Autodesk Fusion 360 part; units mm, degrees
(part 3 of 10)
sketch "Sloped T channel 0 sketch (4)" plane through (22, 0, 0) normal (1, 0, 0) x (0, 0, -1) in component "Horizontal tie 00 - measured sloped-slot approximation"
  line L0 (-15, 8.86) -> (-16.5, 8.86)
  line L1 (-16.5, 8.86) -> (-16.5, 6.5)
  line L2 (-16.5, 6.5) -> (-18.55, 6.5)
  line L3 (-18.55, 6.5) -> (-21.2, 9.15)
  line L4 (-21.2, 9.15) -> (-21.2, 14.85)
  line L5 (-21.2, 14.85) -> (-18.55, 17.5)
  line L6 (-18.55, 17.5) -> (-16.5, 17.5)
  line L7 (-16.5, 17.5) -> (-16.5, 15.14)
  line L8 (-16.5, 15.14) -> (-15, 15.14)
  line L9 (-15, 15.14) -> (-15, 8.86)
  dimension "d922" = 15
  dimension "d923" = 8.86
  dimension "d924" = 16.5
  dimension "d925" = 6.5
  dimension "d926" = 18.55
  dimension "d927" = 21.2
  dimension "d928" = 9.15
  dimension "d929" = 14.85
  dimension "d930" = 17.5
  dimension "d931" = 15.14
  constraint horizontal L0.start L0.end
  constraint vertical L0.end L1.end
  constraint horizontal L1.end L2.end
  constraint vertical L3.end L4.end
  constraint vertical L2.end L5.end
  constraint vertical L1.end L6.end
  constraint horizontal L5.end L6.end
  constraint vertical L6.end L7.end
  constraint vertical L0.start L8.end
  constraint horizontal L7.end L8.end
  measures "d922" horizontal distance of origin L0.start
  measures "d923" vertical distance of origin L0.start
  measures "d924" horizontal distance of origin L0.end
  measures "d925" vertical distance of origin L1.end
  measures "d926" horizontal distance of origin L2.end
  measures "d927" horizontal distance of origin L3.end
  measures "d928" vertical distance of origin L3.end
  measures "d929" vertical distance of origin L4.end
  measures "d930" vertical distance of origin L5.end
  measures "d931" vertical distance of origin L7.end
extrude "Sloped T channel 0'''" cut sketch "Sloped T channel 0 sketch (4)" along normal blind 88 bodies 8 in component "Horizontal tie 00 - measured sloped-slot approximation"
ref_plane "WorkPlane3" through (22, 0, 0) normal (1, 0, 0) x (0, 1, 0) in component "Horizontal tie 00 - measured sloped-slot approximation"
sketch "Sloped T channel 1 sketch (4)" plane through (22, 0, 0) normal (1, 0, 0) x (0, 0, -1) in component "Horizontal tie 00 - measured sloped-slot approximation"
  line L0 (-21.86, 22) -> (-21.86, 20.5)
  line L1 (-21.86, 20.5) -> (-19.5, 20.5)
  line L2 (-19.5, 20.5) -> (-19.5, 18.45)
  line L3 (-19.5, 18.45) -> (-22.15, 15.8)
  line L4 (-22.15, 15.8) -> (-27.85, 15.8)
  line L5 (-27.85, 15.8) -> (-30.5, 18.45)
  line L6 (-30.5, 18.45) -> (-30.5, 20.5)
  line L7 (-30.5, 20.5) -> (-28.14, 20.5)
  line L8 (-28.14, 20.5) -> (-28.14, 22)
  line L9 (-28.14, 22) -> (-21.86, 22)
  dimension "d936" = 21.86
  dimension "d937" = 22
  dimension "d938" = 20.5
  dimension "d939" = 19.5
  dimension "d940" = 18.45
  dimension "d941" = 22.15
  dimension "d942" = 15.8
  dimension "d943" = 27.85
  dimension "d944" = 30.5
  dimension "d945" = 28.14
  constraint vertical L0.start L0.end
  constraint horizontal L0.end L1.end
  constraint vertical L1.end L2.end
  constraint horizontal L3.end L4.end
  constraint horizontal L2.end L5.end
  constraint vertical L5.end L6.end
  constraint horizontal L1.end L6.end
  constraint horizontal L6.end L7.end
  constraint vertical L7.end L8.end
  constraint horizontal L0.start L8.end
  measures "d936" horizontal distance of origin L0.start
  measures "d937" vertical distance of origin L0.start
  measures "d938" vertical distance of origin L0.end
  measures "d939" horizontal distance of origin L1.end
  measures "d940" vertical distance of origin L2.end
  measures "d941" horizontal distance of origin L3.end
  measures "d942" vertical distance of origin L3.end
  measures "d943" horizontal distance of origin L4.end
  measures "d944" horizontal distance of origin L5.end
  measures "d945" horizontal distance of origin L7.end
extrude "Sloped T channel 1'''" cut sketch "Sloped T channel 1 sketch (4)" along normal blind 88 bodies 8 in component "Horizontal tie 00 - measured sloped-slot approximation"
ref_plane "WorkPlane4" through (22, 0, 0) normal (1, 0, 0) x (0, 1, 0) in component "Horizontal tie 00 - measured sloped-slot approximation"
sketch "Sloped T channel 2 sketch (4)" plane through (22, 0, 0) normal (1, 0, 0) x (0, 0, -1) in component "Horizontal tie 00 - measured sloped-slot approximation"
  line L0 (-35, 15.14) -> (-33.5, 15.14)
  line L1 (-33.5, 15.14) -> (-33.5, 17.5)
  line L2 (-33.5, 17.5) -> (-31.45, 17.5)
  line L3 (-31.45, 17.5) -> (-28.8, 14.85)
  line L4 (-28.8, 14.85) -> (-28.8, 9.15)
  line L5 (-28.8, 9.15) -> (-31.45, 6.5)
  line L6 (-31.45, 6.5) -> (-33.5, 6.5)
  line L7 (-33.5, 6.5) -> (-33.5, 8.86)
  line L8 (-33.5, 8.86) -> (-35, 8.86)
  line L9 (-35, 8.86) -> (-35, 15.14)
  dimension "d950" = 35
  dimension "d951" = 15.14
  dimension "d952" = 33.5
  dimension "d953" = 17.5
  dimension "d954" = 31.45
  dimension "d955" = 28.8
  dimension "d956" = 14.85
  dimension "d957" = 9.15
  dimension "d958" = 6.5
  dimension "d959" = 8.86
  constraint horizontal L0.start L0.end
  constraint vertical L0.end L1.end
  constraint horizontal L1.end L2.end
  constraint vertical L3.end L4.end
  constraint vertical L2.end L5.end
  constraint vertical L1.end L6.end
  constraint horizontal L5.end L6.end
  constraint vertical L6.end L7.end
  constraint vertical L0.start L8.end
  constraint horizontal L7.end L8.end
  measures "d950" horizontal distance of origin L0.start
  measures "d951" vertical distance of origin L0.start
  measures "d952" horizontal distance of origin L0.end
  measures "d953" vertical distance of origin L1.end
  measures "d954" horizontal distance of origin L2.end
  measures "d955" horizontal distance of origin L3.end
  measures "d956" vertical distance of origin L3.end
  measures "d957" vertical distance of origin L4.end
  measures "d958" vertical distance of origin L5.end
  measures "d959" vertical distance of origin L7.end
extrude "Sloped T channel 2'''" cut sketch "Sloped T channel 2 sketch (4)" along normal blind 88 bodies 8 in component "Horizontal tie 00 - measured sloped-slot approximation"
ref_plane "WorkPlane5" through (22, 0, 0) normal (1, 0, 0) x (0, 1, 0) in component "Horizontal tie 00 - measured sloped-slot approximation"
sketch "Sloped T channel 3 sketch (4)" plane through (22, 0, 0) normal (1, 0, 0) x (0, 0, -1) in component "Horizontal tie 00 - measured sloped-slot approximation"
  line L0 (-28.14, 2) -> (-28.14, 3.5)
  line L1 (-28.14, 3.5) -> (-30.5, 3.5)
  line L2 (-30.5, 3.5) -> (-30.5, 5.55)
  line L3 (-30.5, 5.55) -> (-27.85, 8.2)
  line L4 (-27.85, 8.2) -> (-22.15, 8.2)
  line L5 (-22.15, 8.2) -> (-19.5, 5.55)
  line L6 (-19.5, 5.55) -> (-19.5, 3.5)
  line L7 (-19.5, 3.5) -> (-21.86, 3.5)
  line L8 (-21.86, 3.5) -> (-21.86, 2)
  line L9 (-21.86, 2) -> (-28.14, 2)
  dimension "d964" = 28.14
  dimension "d965" = 2
  dimension "d966" = 3.5
  dimension "d967" = 30.5
  dimension "d968" = 5.55
  dimension "d969" = 27.85
  dimension "d970" = 8.2
  dimension "d971" = 22.15
  dimension "d972" = 19.5
  dimension "d973" = 21.86
  constraint vertical L0.start L0.end
  constraint horizontal L0.end L1.end
  constraint vertical L1.end L2.end
  constraint horizontal L3.end L4.end
  constraint horizontal L2.end L5.end
  constraint vertical L5.end L6.end
  constraint horizontal L1.end L6.end
  constraint horizontal L6.end L7.end
  constraint vertical L7.end L8.end
  constraint horizontal L0.start L8.end
  measures "d964" horizontal distance of origin L0.start
  measures "d965" vertical distance of origin L0.start
  measures "d966" vertical distance of origin L0.end
  measures "d967" horizontal distance of origin L1.end
  measures "d968" vertical distance of origin L2.end
  measures "d969" horizontal distance of origin L3.end
  measures "d970" vertical distance of origin L3.end
  measures "d971" horizontal distance of origin L4.end
  measures "d972" horizontal distance of origin L5.end
  measures "d973" horizontal distance of origin L7.end
extrude "Sloped T channel 3'''" cut sketch "Sloped T channel 3 sketch (4)" along normal blind 88 bodies 8 in component "Horizontal tie 00 - measured sloped-slot approximation"
ref_plane "WorkPlane6" through (22, 0, 0) normal (1, 0, 0) x (0, 1, 0) in component "Horizontal tie 00 - measured sloped-slot approximation"
sketch "Reference center bore sketch (4)" plane through (22, 0, 0) normal (1, 0, 0) x (0, 0, -1) in component "Horizontal tie 00 - measured sloped-slot approximation"
  circle A0 centre (-25, 12) radius 2.5
  dimension "d978" = 25
  dimension "d979" = 12
  dimension "d980" = 5
  measures "d978" horizontal distance of origin A0.centre
  measures "d979" vertical distance of origin A0.centre
  measures "d980" diameter of A0
extrude "Reference center bore'''" cut sketch "Reference center bore sketch (4)" along normal blind 88 bodies 8 in component "Horizontal tie 00 - measured sloped-slot approximation"
ref_plane "WorkPlane1" through (130, 0, 0) normal (1, 0, 0) x (0, 1, 0) in component "Horizontal tie 10 - measured sloped-slot approximation"
sketch "Profile blank sketch (5)" plane through (130, 0, 0) normal (1, 0, 0) x (0, 0, -1) in component "Horizontal tie 10 - measured sloped-slot approximation"
  line L0 (-15, 2) -> (-15, 22)
  line L1 (-15, 22) -> (-35, 22)
  line L2 (-35, 22) -> (-35, 2)
  line L3 (-35, 2) -> (-15, 2)
  dimension "d985" = 15
  dimension "d986" = 2
  dimension "d987" = 22
  dimension "d988" = 35
  constraint vertical L0.start L0.end
  constraint horizontal L0.end L1.end
  constraint vertical L1.end L2.end
  constraint horizontal L0.start L2.end
  measures "d985" horizontal distance of origin L0.start
  measures "d986" vertical distance of origin L0.start
  measures "d987" vertical distance of origin L0.end
  measures "d988" horizontal distance of origin L1.end
extrude "Profile blank''''" add sketch "Profile blank sketch (5)" along normal blind 88 separate body makes body 9 in component "Horizontal tie 10 - measured sloped-slot approximation"
ref_plane "WorkPlane2" through (130, 0, 0) normal (1, 0, 0) x (0, 1, 0) in component "Horizontal tie 10 - measured sloped-slot approximation"
sketch "Sloped T channel 0 sketch (5)" plane through (130, 0, 0) normal (1, 0, 0) x (0, 0, -1) in component "Horizontal tie 10 - measured sloped-slot approximation"
  line L0 (-15, 8.86) -> (-16.5, 8.86)
  line L1 (-16.5, 8.86) -> (-16.5, 6.5)
  line L2 (-16.5, 6.5) -> (-18.55, 6.5)
  line L3 (-18.55, 6.5) -> (-21.2, 9.15)
  line L4 (-21.2, 9.15) -> (-21.2, 14.85)
  line L5 (-21.2, 14.85) -> (-18.55, 17.5)
  line L6 (-18.55, 17.5) -> (-16.5, 17.5)
  line L7 (-16.5, 17.5) -> (-16.5, 15.14)
  line L8 (-16.5, 15.14) -> (-15, 15.14)
  line L9 (-15, 15.14) -> (-15, 8.86)
  dimension "d993" = 15
  dimension "d994" = 8.86
  dimension "d995" = 16.5
  dimension "d996" = 6.5
  dimension "d997" = 18.55
  dimension "d998" = 21.2
  dimension "d999" = 9.15
  dimension "d1000" = 14.85
  dimension "d1001" = 17.5
  dimension "d1002" = 15.14
  constraint horizontal L0.start L0.end
  constraint vertical L0.end L1.end
  constraint horizontal L1.end L2.end
  constraint vertical L3.end L4.end
  constraint vertical L2.end L5.end
  constraint vertical L1.end L6.end
  constraint horizontal L5.end L6.end
  constraint vertical L6.end L7.end
  constraint vertical L0.start L8.end
  constraint horizontal L7.end L8.end
  measures "d993" horizontal distance of origin L0.start
  measures "d994" vertical distance of origin L0.start
  measures "d995" horizontal distance of origin L0.end
  measures "d996" vertical distance of origin L1.end
  measures "d997" horizontal distance of origin L2.end
  measures "d998" horizontal distance of origin L3.end
  measures "d999" vertical distance of origin L3.end
  measures "d1000" vertical distance of origin L4.end
  measures "d1001" vertical distance of origin L5.end
  measures "d1002" vertical distance of origin L7.end
extrude "Sloped T channel 0''''" cut sketch "Sloped T channel 0 sketch (5)" along normal blind 88 bodies 9 in component "Horizontal tie 10 - measured sloped-slot approximation"
ref_plane "WorkPlane3" through (130, 0, 0) normal (1, 0, 0) x (0, 1, 0) in component "Horizontal tie 10 - measured sloped-slot approximation"
sketch "Sloped T channel 1 sketch (5)" plane through (130, 0, 0) normal (1, 0, 0) x (0, 0, -1) in component "Horizontal tie 10 - measured sloped-slot approximation"
  line L0 (-21.86, 22) -> (-21.86, 20.5)
  line L1 (-21.86, 20.5) -> (-19.5, 20.5)
  line L2 (-19.5, 20.5) -> (-19.5, 18.45)
  line L3 (-19.5, 18.45) -> (-22.15, 15.8)
  line L4 (-22.15, 15.8) -> (-27.85, 15.8)
  line L5 (-27.85, 15.8) -> (-30.5, 18.45)
  line L6 (-30.5, 18.45) -> (-30.5, 20.5)
  line L7 (-30.5, 20.5) -> (-28.14, 20.5)
  line L8 (-28.14, 20.5) -> (-28.14, 22)
  line L9 (-28.14, 22) -> (-21.86, 22)
  dimension "d1007" = 21.86
  dimension "d1008" = 22
  dimension "d1009" = 20.5
  dimension "d1010" = 19.5
  dimension "d1011" = 18.45
  dimension "d1012" = 22.15
  dimension "d1013" = 15.8
  dimension "d1014" = 27.85
  dimension "d1015" = 30.5
  dimension "d1016" = 28.14
  constraint vertical L0.start L0.end
  constraint horizontal L0.end L1.end
  constraint vertical L1.end L2.end
  constraint horizontal L3.end L4.end
  constraint horizontal L2.end L5.end
  constraint vertical L5.end L6.end
  constraint horizontal L1.end L6.end
  constraint horizontal L6.end L7.end
  constraint vertical L7.end L8.end
  constraint horizontal L0.start L8.end
  measures "d1007" horizontal distance of origin L0.start
  measures "d1008" vertical distance of origin L0.start
  measures "d1009" vertical distance of origin L0.end
  measures "d1010" horizontal distance of origin L1.end
  measures "d1011" vertical distance of origin L2.end
  measures "d1012" horizontal distance of origin L3.end
  measures "d1013" vertical distance of origin L3.end
  measures "d1014" horizontal distance of origin L4.end
  measures "d1015" horizontal distance of origin L5.end
  measures "d1016" horizontal distance of origin L7.end
extrude "Sloped T channel 1''''" cut sketch "Sloped T channel 1 sketch (5)" along normal blind 88 bodies 9 in component "Horizontal tie 10 - measured sloped-slot approximation"
ref_plane "WorkPlane4" through (130, 0, 0) normal (1, 0, 0) x (0, 1, 0) in component "Horizontal tie 10 - measured sloped-slot approximation"
sketch "Sloped T channel 2 sketch (5)" plane through (130, 0, 0) normal (1, 0, 0) x (0, 0, -1) in component "Horizontal tie 10 - measured sloped-slot approximation"
  line L0 (-35, 15.14) -> (-33.5, 15.14)
  line L1 (-33.5, 15.14) -> (-33.5, 17.5)
  line L2 (-33.5, 17.5) -> (-31.45, 17.5)
  line L3 (-31.45, 17.5) -> (-28.8, 14.85)
  line L4 (-28.8, 14.85) -> (-28.8, 9.15)
  line L5 (-28.8, 9.15) -> (-31.45, 6.5)
  line L6 (-31.45, 6.5) -> (-33.5, 6.5)
  line L7 (-33.5, 6.5) -> (-33.5, 8.86)
  line L8 (-33.5, 8.86) -> (-35, 8.86)
  line L9 (-35, 8.86) -> (-35, 15.14)
  dimension "d1021" = 35
  dimension "d1022" = 15.14
  dimension "d1023" = 33.5
  dimension "d1024" = 17.5
  dimension "d1025" = 31.45
  dimension "d1026" = 28.8
  dimension "d1027" = 14.85
  dimension "d1028" = 9.15
  dimension "d1029" = 6.5
  dimension "d1030" = 8.86
  constraint horizontal L0.start L0.end
  constraint vertical L0.end L1.end
  constraint horizontal L1.end L2.end
  constraint vertical L3.end L4.end
  constraint vertical L2.end L5.end
  constraint vertical L1.end L6.end
  constraint horizontal L5.end L6.end
  constraint vertical L6.end L7.end
  constraint vertical L0.start L8.end
  constraint horizontal L7.end L8.end
  measures "d1021" horizontal distance of origin L0.start
  measures "d1022" vertical distance of origin L0.start
  measures "d1023" horizontal distance of origin L0.end
  measures "d1024" vertical distance of origin L1.end
  measures "d1025" horizontal distance of origin L2.end
  measures "d1026" horizontal distance of origin L3.end
  measures "d1027" vertical distance of origin L3.end
  measures "d1028" vertical distance of origin L4.end
  measures "d1029" vertical distance of origin L5.end
  measures "d1030" vertical distance of origin L7.end
extrude "Sloped T channel 2''''" cut sketch "Sloped T channel 2 sketch (5)" along normal blind 88 bodies 9 in component "Horizontal tie 10 - measured sloped-slot approximation"
ref_plane "WorkPlane5" through (130, 0, 0) normal (1, 0, 0) x (0, 1, 0) in component "Horizontal tie 10 - measured sloped-slot approximation"
sketch "Sloped T channel 3 sketch (5)" plane through (130, 0, 0) normal (1, 0, 0) x (0, 0, -1) in component "Horizontal tie 10 - measured sloped-slot approximation"
  line L0 (-28.14, 2) -> (-28.14, 3.5)
  line L1 (-28.14, 3.5) -> (-30.5, 3.5)
  line L2 (-30.5, 3.5) -> (-30.5, 5.55)
  line L3 (-30.5, 5.55) -> (-27.85, 8.2)
  line L4 (-27.85, 8.2) -> (-22.15, 8.2)
  line L5 (-22.15, 8.2) -> (-19.5, 5.55)
  line L6 (-19.5, 5.55) -> (-19.5, 3.5)
  line L7 (-19.5, 3.5) -> (-21.86, 3.5)
  line L8 (-21.86, 3.5) -> (-21.86, 2)
  line L9 (-21.86, 2) -> (-28.14, 2)
  dimension "d1035" = 28.14
  dimension "d1036" = 2
  dimension "d1037" = 3.5
  dimension "d1038" = 30.5
  dimension "d1039" = 5.55
  dimension "d1040" = 27.85
  dimension "d1041" = 8.2
  dimension "d1042" = 22.15
  dimension "d1043" = 19.5
  dimension "d1044" = 21.86
  constraint vertical L0.start L0.end
  constraint horizontal L0.end L1.end
  constraint vertical L1.end L2.end
  constraint horizontal L3.end L4.end
  constraint horizontal L2.end L5.end
  constraint vertical L5.end L6.end
  constraint horizontal L1.end L6.end
  constraint horizontal L6.end L7.end
  constraint vertical L7.end L8.end
  constraint horizontal L0.start L8.end
  measures "d1035" horizontal distance of origin L0.start
  measures "d1036" vertical distance of origin L0.start
  measures "d1037" vertical distance of origin L0.end
  measures "d1038" horizontal distance of origin L1.end
  measures "d1039" vertical distance of origin L2.end
  measures "d1040" horizontal distance of origin L3.end
  measures "d1041" vertical distance of origin L3.end
  measures "d1042" horizontal distance of origin L4.end
  measures "d1043" horizontal distance of origin L5.end
  measures "d1044" horizontal distance of origin L7.end
extrude "Sloped T channel 3''''" cut sketch "Sloped T channel 3 sketch (5)" along normal blind 88 bodies 9 in component "Horizontal tie 10 - measured sloped-slot approximation"
ref_plane "WorkPlane6" through (130, 0, 0) normal (1, 0, 0) x (0, 1, 0) in component "Horizontal tie 10 - measured sloped-slot approximation"
sketch "Reference center bore sketch (5)" plane through (130, 0, 0) normal (1, 0, 0) x (0, 0, -1) in component "Horizontal tie 10 - measured sloped-slot approximation"
  circle A0 centre (-25, 12) radius 2.5
  dimension "d1049" = 25
  dimension "d1050" = 12
  dimension "d1051" = 5
  measures "d1049" horizontal distance of origin A0.centre
  measures "d1050" vertical distance of origin A0.centre
  measures "d1051" diameter of A0
extrude "Reference center bore''''" cut sketch "Reference center bore sketch (5)" along normal blind 88 bodies 9 in component "Horizontal tie 10 - measured sloped-slot approximation"
ref_plane "WorkPlane1" through (22, 0, 0) normal (1, 0, 0) x (0, 1, 0) in component "Horizontal tie 01 - measured sloped-slot approximation"
sketch "Profile blank sketch (6)" plane through (22, 0, 0) normal (1, 0, 0) x (0, 0, -1) in component "Horizontal tie 01 - measured sloped-slot approximation"
  line L0 (-15, 218) -> (-15, 238)
  line L1 (-15, 238) -> (-35, 238)
  line L2 (-35, 238) -> (-35, 218)
  line L3 (-35, 218) -> (-15, 218)
  dimension "d1056" = 15
  dimension "d1057" = 218
  dimension "d1058" = 238
  dimension "d1059" = 35
  constraint vertical L0.start L0.end
  constraint horizontal L0.end L1.end
  constraint vertical L1.end L2.end
  constraint horizontal L0.start L2.end
  measures "d1056" horizontal distance of origin L0.start
  measures "d1057" vertical distance of origin L0.start
  measures "d1058" vertical distance of origin L0.end
  measures "d1059" horizontal distance of origin L1.end
extrude "Profile blank'''''" add sketch "Profile blank sketch (6)" along normal blind 88 separate body makes body 10 in component "Horizontal tie 01 - measured sloped-slot approximation"
ref_plane "WorkPlane2" through (22, 0, 0) normal (1, 0, 0) x (0, 1, 0) in component "Horizontal tie 01 - measured sloped-slot approximation"
sketch "Sloped T channel 0 sketch (6)" plane through (22, 0, 0) normal (1, 0, 0) x (0, 0, -1) in component "Horizontal tie 01 - measured sloped-slot approximation"
  line L0 (-15, 224.86) -> (-16.5, 224.86)
  line L1 (-16.5, 224.86) -> (-16.5, 222.5)
  line L2 (-16.5, 222.5) -> (-18.55, 222.5)
  line L3 (-18.55, 222.5) -> (-21.2, 225.15)
  line L4 (-21.2, 225.15) -> (-21.2, 230.85)
  line L5 (-21.2, 230.85) -> (-18.55, 233.5)
  line L6 (-18.55, 233.5) -> (-16.5, 233.5)
  line L7 (-16.5, 233.5) -> (-16.5, 231.14)
  line L8 (-16.5, 231.14) -> (-15, 231.14)
  line L9 (-15, 231.14) -> (-15, 224.86)
  dimension "d1064" = 15
  dimension "d1065" = 224.86
  dimension "d1066" = 16.5
  dimension "d1067" = 222.5
  dimension "d1068" = 18.55
  dimension "d1069" = 21.2
  dimension "d1070" = 225.15
  dimension "d1071" = 230.85
  dimension "d1072" = 233.5
  dimension "d1073" = 231.14
  constraint horizontal L0.start L0.end
  constraint vertical L0.end L1.end
  constraint horizontal L1.end L2.end
  constraint vertical L3.end L4.end
  constraint vertical L2.end L5.end
  constraint vertical L1.end L6.end
  constraint horizontal L5.end L6.end
  constraint vertical L6.end L7.end
  constraint vertical L0.start L8.end
  constraint horizontal L7.end L8.end
  measures "d1064" horizontal distance of origin L0.start
  measures "d1065" vertical distance of origin L0.start
  measures "d1066" horizontal distance of origin L0.end
  measures "d1067" vertical distance of origin L1.end
  measures "d1068" horizontal distance of origin L2.end
  measures "d1069" horizontal distance of origin L3.end
  measures "d1070" vertical distance of origin L3.end
  measures "d1071" vertical distance of origin L4.end
  measures "d1072" vertical distance of origin L5.end
  measures "d1073" vertical distance of origin L7.end
extrude "Sloped T channel 0'''''" cut sketch "Sloped T channel 0 sketch (6)" along normal blind 88 bodies 10 in component "Horizontal tie 01 - measured sloped-slot approximation"
ref_plane "WorkPlane3" through (22, 0, 0) normal (1, 0, 0) x (0, 1, 0) in component "Horizontal tie 01 - measured sloped-slot approximation"
sketch "Sloped T channel 1 sketch (6)" plane through (22, 0, 0) normal (1, 0, 0) x (0, 0, -1) in component "Horizontal tie 01 - measured sloped-slot approximation"
  line L0 (-21.86, 238) -> (-21.86, 236.5)
  line L1 (-21.86, 236.5) -> (-19.5, 236.5)
  line L2 (-19.5, 236.5) -> (-19.5, 234.45)
  line L3 (-19.5, 234.45) -> (-22.15, 231.8)
  line L4 (-22.15, 231.8) -> (-27.85, 231.8)
  line L5 (-27.85, 231.8) -> (-30.5, 234.45)
  line L6 (-30.5, 234.45) -> (-30.5, 236.5)
  line L7 (-30.5, 236.5) -> (-28.14, 236.5)
  line L8 (-28.14, 236.5) -> (-28.14, 238)
  line L9 (-28.14, 238) -> (-21.86, 238)
  dimension "d1078" = 21.86
  dimension "d1079" = 238
  dimension "d1080" = 236.5
  dimension "d1081" = 19.5
  dimension "d1082" = 234.45
  dimension "d1083" = 22.15
  dimension "d1084" = 231.8
  dimension "d1085" = 27.85
  dimension "d1086" = 30.5
  dimension "d1087" = 28.14
  constraint vertical L0.start L0.end
  constraint horizontal L0.end L1.end
  constraint vertical L1.end L2.end
  constraint horizontal L3.end L4.end
  constraint horizontal L2.end L5.end
  constraint vertical L5.end L6.end
  constraint horizontal L1.end L6.end
  constraint horizontal L6.end L7.end
  constraint vertical L7.end L8.end
  constraint horizontal L0.start L8.end
  measures "d1078" horizontal distance of origin L0.start
  measures "d1079" vertical distance of origin L0.start
  measures "d1080" vertical distance of origin L0.end
  measures "d1081" horizontal distance of origin L1.end
  measures "d1082" vertical distance of origin L2.end
  measures "d1083" horizontal distance of origin L3.end
  measures "d1084" vertical distance of origin L3.end
  measures "d1085" horizontal distance of origin L4.end
  measures "d1086" horizontal distance of origin L5.end
  measures "d1087" horizontal distance of origin L7.end
extrude "Sloped T channel 1'''''" cut sketch "Sloped T channel 1 sketch (6)" along normal blind 88 bodies 10 in component "Horizontal tie 01 - measured sloped-slot approximation"
ref_plane "WorkPlane4" through (22, 0, 0) normal (1, 0, 0) x (0, 1, 0) in component "Horizontal tie 01 - measured sloped-slot approximation"
sketch "Sloped T channel 2 sketch (6)" plane through (22, 0, 0) normal (1, 0, 0) x (0, 0, -1) in component "Horizontal tie 01 - measured sloped-slot approximation"
  line L0 (-35, 231.14) -> (-33.5, 231.14)
  line L1 (-33.5, 231.14) -> (-33.5, 233.5)
  line L2 (-33.5, 233.5) -> (-31.45, 233.5)
  line L3 (-31.45, 233.5) -> (-28.8, 230.85)
  line L4 (-28.8, 230.85) -> (-28.8, 225.15)
  line L5 (-28.8, 225.15) -> (-31.45, 222.5)
  line L6 (-31.45, 222.5) -> (-33.5, 222.5)
  line L7 (-33.5, 222.5) -> (-33.5, 224.86)
  line L8 (-33.5, 224.86) -> (-35, 224.86)
  line L9 (-35, 224.86) -> (-35, 231.14)
  dimension "d1092" = 35
  dimension "d1093" = 231.14
  dimension "d1094" = 33.5
  dimension "d1095" = 233.5
  dimension "d1096" = 31.45
  dimension "d1097" = 28.8
  dimension "d1098" = 230.85
  dimension "d1099" = 225.15
  dimension "d1100" = 222.5
  dimension "d1101" = 224.86
  constraint horizontal L0.start L0.end
  constraint vertical L0.end L1.end
  constraint horizontal L1.end L2.end
  constraint vertical L3.end L4.end
  constraint vertical L2.end L5.end
  constraint vertical L1.end L6.end
  constraint horizontal L5.end L6.end
  constraint vertical L6.end L7.end
  constraint vertical L0.start L8.end
  constraint horizontal L7.end L8.end
  measures "d1092" horizontal distance of origin L0.start
  measures "d1093" vertical distance of origin L0.start
  measures "d1094" horizontal distance of origin L0.end
  measures "d1095" vertical distance of origin L1.end
  measures "d1096" horizontal distance of origin L2.end
  measures "d1097" horizontal distance of origin L3.end
  measures "d1098" vertical distance of origin L3.end
  measures "d1099" vertical distance of origin L4.end
  measures "d1100" vertical distance of origin L5.end
  measures "d1101" vertical distance of origin L7.end
extrude "Sloped T channel 2'''''" cut sketch "Sloped T channel 2 sketch (6)" along normal blind 88 bodies 10 in component "Horizontal tie 01 - measured sloped-slot approximation"
ref_plane "WorkPlane5" through (22, 0, 0) normal (1, 0, 0) x (0, 1, 0) in component "Horizontal tie 01 - measured sloped-slot approximation"
sketch "Sloped T channel 3 sketch (6)" plane through (22, 0, 0) normal (1, 0, 0) x (0, 0, -1) in component "Horizontal tie 01 - measured sloped-slot approximation"
  line L0 (-28.14, 218) -> (-28.14, 219.5)
  line L1 (-28.14, 219.5) -> (-30.5, 219.5)
  line L2 (-30.5, 219.5) -> (-30.5, 221.55)
  line L3 (-30.5, 221.55) -> (-27.85, 224.2)
  line L4 (-27.85, 224.2) -> (-22.15, 224.2)
  line L5 (-22.15, 224.2) -> (-19.5, 221.55)
  line L6 (-19.5, 221.55) -> (-19.5, 219.5)
  line L7 (-19.5, 219.5) -> (-21.86, 219.5)
  line L8 (-21.86, 219.5) -> (-21.86, 218)
  line L9 (-21.86, 218) -> (-28.14, 218)
  dimension "d1106" = 28.14
  dimension "d1107" = 218
  dimension "d1108" = 219.5
  dimension "d1109" = 30.5
  dimension "d1110" = 221.55
  dimension "d1111" = 27.85
  dimension "d1112" = 224.2
  dimension "d1113" = 22.15
  dimension "d1114" = 19.5
  dimension "d1115" = 21.86
  constraint vertical L0.start L0.end
  constraint horizontal L0.end L1.end
  constraint vertical L1.end L2.end
  constraint horizontal L3.end L4.end
  constraint horizontal L2.end L5.end
  constraint vertical L5.end L6.end
  constraint horizontal L1.end L6.end
  constraint horizontal L6.end L7.end
  constraint vertical L7.end L8.end
  constraint horizontal L0.start L8.end
  measures "d1106" horizontal distance of origin L0.start
  measures "d1107" vertical distance of origin L0.start
  measures "d1108" vertical distance of origin L0.end
  measures "d1109" horizontal distance of origin L1.end
  measures "d1110" vertical distance of origin L2.end
  measures "d1111" horizontal distance of origin L3.end
  measures "d1112" vertical distance of origin L3.end
  measures "d1113" horizontal distance of origin L4.end
  measures "d1114" horizontal distance of origin L5.end
  measures "d1115" horizontal distance of origin L7.end
extrude "Sloped T channel 3'''''" cut sketch "Sloped T channel 3 sketch (6)" along normal blind 88 bodies 10 in component "Horizontal tie 01 - measured sloped-slot approximation"
ref_plane "WorkPlane6" through (22, 0, 0) normal (1, 0, 0) x (0, 1, 0) in component "Horizontal tie 01 - measured sloped-slot approximation"
sketch "Reference center bore sketch (6)" plane through (22, 0, 0) normal (1, 0, 0) x (0, 0, -1) in component "Horizontal tie 01 - measured sloped-slot approximation"
  circle A0 centre (-25, 228) radius 2.5
  dimension "d1120" = 25
  dimension "d1121" = 228
  dimension "d1122" = 5
  measures "d1120" horizontal distance of origin A0.centre
  measures "d1121" vertical distance of origin A0.centre
  measures "d1122" diameter of A0
extrude "Reference center bore'''''" cut sketch "Reference center bore sketch (6)" along normal blind 88 bodies 10 in component "Horizontal tie 01 - measured sloped-slot approximation"
ref_plane "WorkPlane1" through (130, 0, 0) normal (1, 0, 0) x (0, 1, 0) in component "Horizontal tie 11 - measured sloped-slot approximation"
sketch "Profile blank sketch (7)" plane through (130, 0, 0) normal (1, 0, 0) x (0, 0, -1) in component "Horizontal tie 11 - measured sloped-slot approximation"
  line L0 (-15, 218) -> (-15, 238)
  line L1 (-15, 238) -> (-35, 238)
  line L2 (-35, 238) -> (-35, 218)
  line L3 (-35, 218) -> (-15, 218)
  dimension "d1127" = 15
  dimension "d1128" = 218
  dimension "d1129" = 238
  dimension "d1130" = 35
  constraint vertical L0.start L0.end
  constraint horizontal L0.end L1.end
  constraint vertical L1.end L2.end
  constraint horizontal L0.start L2.end
  measures "d1127" horizontal distance of origin L0.start
  measures "d1128" vertical distance of origin L0.start
  measures "d1129" vertical distance of origin L0.end
  measures "d1130" horizontal distance of origin L1.end
extrude "Profile blank''''''" add sketch "Profile blank sketch (7)" along normal blind 88 separate body makes body 11 in component "Horizontal tie 11 - measured sloped-slot approximation"
ref_plane "WorkPlane2" through (130, 0, 0) normal (1, 0, 0) x (0, 1, 0) in component "Horizontal tie 11 - measured sloped-slot approximation"
sketch "Sloped T channel 0 sketch (7)" plane through (130, 0, 0) normal (1, 0, 0) x (0, 0, -1) in component "Horizontal tie 11 - measured sloped-slot approximation"
  line L0 (-15, 224.86) -> (-16.5, 224.86)
  line L1 (-16.5, 224.86) -> (-16.5, 222.5)
  line L2 (-16.5, 222.5) -> (-18.55, 222.5)
  line L3 (-18.55, 222.5) -> (-21.2, 225.15)
  line L4 (-21.2, 225.15) -> (-21.2, 230.85)
  line L5 (-21.2, 230.85) -> (-18.55, 233.5)
  line L6 (-18.55, 233.5) -> (-16.5, 233.5)
  line L7 (-16.5, 233.5) -> (-16.5, 231.14)
  line L8 (-16.5, 231.14) -> (-15, 231.14)
  line L9 (-15, 231.14) -> (-15, 224.86)
  dimension "d1135" = 15
  dimension "d1136" = 224.86
  dimension "d1137" = 16.5
  dimension "d1138" = 222.5
  dimension "d1139" = 18.55
  dimension "d1140" = 21.2
  dimension "d1141" = 225.15
  dimension "d1142" = 230.85
  dimension "d1143" = 233.5
  dimension "d1144" = 231.14
  constraint horizontal L0.start L0.end
  constraint vertical L0.end L1.end
  constraint horizontal L1.end L2.end
  constraint vertical L3.end L4.end
  constraint vertical L2.end L5.end
  constraint vertical L1.end L6.end
  constraint horizontal L5.end L6.end
  constraint vertical L6.end L7.end
  constraint vertical L0.start L8.end
  constraint horizontal L7.end L8.end
  measures "d1135" horizontal distance of origin L0.start
  measures "d1136" vertical distance of origin L0.start
  measures "d1137" horizontal distance of origin L0.end
  measures "d1138" vertical distance of origin L1.end
  measures "d1139" horizontal distance of origin L2.end
  measures "d1140" horizontal distance of origin L3.end
  measures "d1141" vertical distance of origin L3.end
  measures "d1142" vertical distance of origin L4.end
  measures "d1143" vertical distance of origin L5.end
  measures "d1144" vertical distance of origin L7.end
extrude "Sloped T channel 0''''''" cut sketch "Sloped T channel 0 sketch (7)" along normal blind 88 bodies 11 in component "Horizontal tie 11 - measured sloped-slot approximation"
ref_plane "WorkPlane3" through (130, 0, 0) normal (1, 0, 0) x (0, 1, 0) in component "Horizontal tie 11 - measured sloped-slot approximation"
sketch "Sloped T channel 1 sketch (7)" plane through (130, 0, 0) normal (1, 0, 0) x (0, 0, -1) in component "Horizontal tie 11 - measured sloped-slot approximation"
  line L0 (-21.86, 238) -> (-21.86, 236.5)
  line L1 (-21.86, 236.5) -> (-19.5, 236.5)
  line L2 (-19.5, 236.5) -> (-19.5, 234.45)
  line L3 (-19.5, 234.45) -> (-22.15, 231.8)
  line L4 (-22.15, 231.8) -> (-27.85, 231.8)
  line L5 (-27.85, 231.8) -> (-30.5, 234.45)
  line L6 (-30.5, 234.45) -> (-30.5, 236.5)
  line L7 (-30.5, 236.5) -> (-28.14, 236.5)
  line L8 (-28.14, 236.5) -> (-28.14, 238)
  line L9 (-28.14, 238) -> (-21.86, 238)
  dimension "d1149" = 21.86
  dimension "d1150" = 238
  dimension "d1151" = 236.5
  dimension "d1152" = 19.5
  dimension "d1153" = 234.45
  dimension "d1154" = 22.15
  dimension "d1155" = 231.8
  dimension "d1156" = 27.85
  dimension "d1157" = 30.5
  dimension "d1158" = 28.14
  constraint vertical L0.start L0.end
  constraint horizontal L0.end L1.end
  constraint vertical L1.end L2.end
  constraint horizontal L3.end L4.end
  constraint horizontal L2.end L5.end
  constraint vertical L5.end L6.end
  constraint horizontal L1.end L6.end
  constraint horizontal L6.end L7.end
  constraint vertical L7.end L8.end
  constraint horizontal L0.start L8.end
  measures "d1149" horizontal distance of origin L0.start
  measures "d1150" vertical distance of origin L0.start
  measures "d1151" vertical distance of origin L0.end
  measures "d1152" horizontal distance of origin L1.end
  measures "d1153" vertical distance of origin L2.end
  measures "d1154" horizontal distance of origin L3.end
  measures "d1155" vertical distance of origin L3.end
  measures "d1156" horizontal distance of origin L4.end
  measures "d1157" horizontal distance of origin L5.end
  measures "d1158" horizontal distance of origin L7.end
extrude "Sloped T channel 1''''''" cut sketch "Sloped T channel 1 sketch (7)" along normal blind 88 bodies 11 in component "Horizontal tie 11 - measured sloped-slot approximation"
ref_plane "WorkPlane4" through (130, 0, 0) normal (1, 0, 0) x (0, 1, 0) in component "Horizontal tie 11 - measured sloped-slot approximation"
sketch "Sloped T channel 2 sketch (7)" plane through (130, 0, 0) normal (1, 0, 0) x (0, 0, -1) in component "Horizontal tie 11 - measured sloped-slot approximation"
  line L0 (-35, 231.14) -> (-33.5, 231.14)
  line L1 (-33.5, 231.14) -> (-33.5, 233.5)
  line L2 (-33.5, 233.5) -> (-31.45, 233.5)
  line L3 (-31.45, 233.5) -> (-28.8, 230.85)
  line L4 (-28.8, 230.85) -> (-28.8, 225.15)
  line L5 (-28.8, 225.15) -> (-31.45, 222.5)
  line L6 (-31.45, 222.5) -> (-33.5, 222.5)
  line L7 (-33.5, 222.5) -> (-33.5, 224.86)
  line L8 (-33.5, 224.86) -> (-35, 224.86)
  line L9 (-35, 224.86) -> (-35, 231.14)
  dimension "d1163" = 35
  dimension "d1164" = 231.14
  dimension "d1165" = 33.5
  dimension "d1166" = 233.5
  dimension "d1167" = 31.45
  dimension "d1168" = 28.8
  dimension "d1169" = 230.85
  dimension "d1170" = 225.15
  dimension "d1171" = 222.5
  dimension "d1172" = 224.86
  constraint horizontal L0.start L0.end
  constraint vertical L0.end L1.end
  constraint horizontal L1.end L2.end
  constraint vertical L3.end L4.end
  constraint vertical L2.end L5.end
  constraint vertical L1.end L6.end
  constraint horizontal L5.end L6.end
  constraint vertical L6.end L7.end
  constraint vertical L0.start L8.end
  constraint horizontal L7.end L8.end
  measures "d1163" horizontal distance of origin L0.start
  measures "d1164" vertical distance of origin L0.start
  measures "d1165" horizontal distance of origin L0.end
  measures "d1166" vertical distance of origin L1.end
  measures "d1167" horizontal distance of origin L2.end
  measures "d1168" horizontal distance of origin L3.end
  measures "d1169" vertical distance of origin L3.end
  measures "d1170" vertical distance of origin L4.end
  measures "d1171" vertical distance of origin L5.end
  measures "d1172" vertical distance of origin L7.end
extrude "Sloped T channel 2''''''" cut sketch "Sloped T channel 2 sketch (7)" along normal blind 88 bodies 11 in component "Horizontal tie 11 - measured sloped-slot approximation"
ref_plane "WorkPlane5" through (130, 0, 0) normal (1, 0, 0) x (0, 1, 0) in component "Horizontal tie 11 - measured sloped-slot approximation"
sketch "Sloped T channel 3 sketch (7)" plane through (130, 0, 0) normal (1, 0, 0) x (0, 0, -1) in component "Horizontal tie 11 - measured sloped-slot approximation"
  line L0 (-28.14, 218) -> (-28.14, 219.5)
  line L1 (-28.14, 219.5) -> (-30.5, 219.5)
  line L2 (-30.5, 219.5) -> (-30.5, 221.55)
  line L3 (-30.5, 221.55) -> (-27.85, 224.2)
  line L4 (-27.85, 224.2) -> (-22.15, 224.2)
  line L5 (-22.15, 224.2) -> (-19.5, 221.55)
  line L6 (-19.5, 221.55) -> (-19.5, 219.5)
  line L7 (-19.5, 219.5) -> (-21.86, 219.5)
  line L8 (-21.86, 219.5) -> (-21.86, 218)
  line L9 (-21.86, 218) -> (-28.14, 218)
  dimension "d1177" = 28.14
  dimension "d1178" = 218
  dimension "d1179" = 219.5
  dimension "d1180" = 30.5
  dimension "d1181" = 221.55
  dimension "d1182" = 27.85
  dimension "d1183" = 224.2
  dimension "d1184" = 22.15
  dimension "d1185" = 19.5
  dimension "d1186" = 21.86
  constraint vertical L0.start L0.end
  constraint horizontal L0.end L1.end
  constraint vertical L1.end L2.end
  constraint horizontal L3.end L4.end
  constraint horizontal L2.end L5.end
  constraint vertical L5.end L6.end
  constraint horizontal L1.end L6.end
  constraint horizontal L6.end L7.end
  constraint vertical L7.end L8.end
  constraint horizontal L0.start L8.end
  measures "d1177" horizontal distance of origin L0.start
  measures "d1178" vertical distance of origin L0.start
  measures "d1179" vertical distance of origin L0.end
  measures "d1180" horizontal distance of origin L1.end
  measures "d1181" vertical distance of origin L2.end
  measures "d1182" horizontal distance of origin L3.end
  measures "d1183" vertical distance of origin L3.end
  measures "d1184" horizontal distance of origin L4.end
  measures "d1185" horizontal distance of origin L5.end
  measures "d1186" horizontal distance of origin L7.end
extrude "Sloped T channel 3''''''" cut sketch "Sloped T channel 3 sketch (7)" along normal blind 88 bodies 11 in component "Horizontal tie 11 - measured sloped-slot approximation"
ref_plane "WorkPlane6" through (130, 0, 0) normal (1, 0, 0) x (0, 1, 0) in component "Horizontal tie 11 - measured sloped-slot approximation"
sketch "Reference center bore sketch (7)" plane through (130, 0, 0) normal (1, 0, 0) x (0, 0, -1) in component "Horizontal tie 11 - measured sloped-slot approximation"
  circle A0 centre (-25, 228) radius 2.5
  dimension "d1191" = 25
  dimension "d1192" = 228
  dimension "d1193" = 5
  measures "d1191" horizontal distance of origin A0.centre
  measures "d1192" vertical distance of origin A0.centre
  measures "d1193" diameter of A0
extrude "Reference center bore''''''" cut sketch "Reference center bore sketch (7)" along normal blind 88 bodies 11 in component "Horizontal tie 11 - measured sloped-slot approximation"
ref_plane "WorkPlane1" through (0, 0, -5) normal (0, 0, 1) x (1, 0, 0) in component "METAL cap 00"
sketch "Visible cap sketch" plane through (0, 0, -5) normal (0, 0, 1) x (1, 0, 0) in component "METAL cap 00"
  circle A0 centre (12, 12) radius 9
  dimension "d1302" = 12
  dimension "d1303" = 12
  dimension "d1304" = 18
  measures "d1302" horizontal distance of origin A0.centre
  measures "d1303" vertical distance of origin A0.centre
  measures "d1304" diameter of A0
extrude "Visible cap" add sketch "Visible cap sketch" along normal blind 5 separate body makes body 12 in component "METAL cap 00"
ref_plane "WorkPlane2" through (0, 0, -5) normal (0, 0, 1) x (1, 0, 0) in component "METAL cap 00"
sketch "M5 clearance sketch" plane through (0, 0, -5) normal (0, 0, 1) x (1, 0, 0) in component "METAL cap 00"
  circle A0 centre (12, 12) radius 2.75
  dimension "d1309" = 12
  dimension "d1310" = 12
  dimension "d1311" = 5.5
  measures "d1309" horizontal distance of origin A0.centre
  measures "d1310" vertical distance of origin A0.centre
  measures "d1311" diameter of A0
extrude "M5 clearance" cut sketch "M5 clearance sketch" along normal blind 5 bodies 12 in component "METAL cap 00"
ref_plane "WorkPlane1" through (0, 0, 5) normal (0, 0, 1) x (1, 0, 0) in component "PRINT registration seat 00"
sketch "Rear bearing seat sketch" plane through (0, 0, 5) normal (0, 0, 1) x (1, 0, 0) in component "PRINT registration seat 00"
  circle A0 centre (12, 12) radius 9
  dimension "d1316" = 12
  dimension "d1317" = 12
  dimension "d1318" = 18
  measures "d1316" horizontal distance of origin A0.centre
  measures "d1317" vertical distance of origin A0.centre
  measures "d1318" diameter of A0
extrude "Rear bearing seat" add sketch "Rear bearing seat sketch" along normal blind 2 separate body makes body 13 in component "PRINT registration seat 00"
ref_plane "WorkPlane2" through (0, 0, 5) normal (0, 0, 1) x (1, 0, 0) in component "PRINT registration seat 00"
sketch "Shoulder clearance sketch" plane through (0, 0, 5) normal (0, 0, 1) x (1, 0, 0) in component "PRINT registration seat 00"
  circle A0 centre (12, 12) radius 4.2
  dimension "d1323" = 12
  dimension "d1324" = 12
  dimension "d1325" = 8.4
  measures "d1323" horizontal distance of origin A0.centre
  measures "d1324" vertical distance of origin A0.centre
  measures "d1325" diameter of A0
extrude "Shoulder clearance" cut sketch "Shoulder clearance sketch" along normal blind 2 bodies 13 in component "PRINT registration seat 00"
ref_plane "WorkPlane3" through (0, 0, 5) normal (0, 0, 1) x (1, 0, 0) in component "PRINT registration seat 00"
sketch "Forward registration peg sketch" plane through (0, 0, 5) normal (0, 0, 1) x (1, 0, 0) in component "PRINT registration seat 00"
  circle A0 centre (7, 7) radius 1
  dimension "d1330" = 7
  dimension "d1331" = 7
  dimension "d1332" = 2
  measures "d1330" horizontal distance of origin A0.centre
  measures "d1331" vertical distance of origin A0.centre
  measures "d1332" diameter of A0
extrude "Forward registration peg" add sketch "Forward registration peg sketch" against normal blind 0.8 bodies 13 in component "PRINT registration seat 00"
ref_plane "WorkPlane4" through (0, 0, 5) normal (0, 0, 1) x (1, 0, 0) in component "PRINT registration seat 00"
sketch "Forward registration peg sketch (1)" plane through (0, 0, 5) normal (0, 0, 1) x (1, 0, 0) in component "PRINT registration seat 00"
  circle A0 centre (7, 17) radius 1
  dimension "d1337" = 7
  dimension "d1338" = 17
  dimension "d1339" = 2
  measures "d1337" horizontal distance of origin A0.centre
  measures "d1338" vertical distance of origin A0.centre
  measures "d1339" diameter of A0
extrude "Forward registration peg (1)" add sketch "Forward registration peg sketch (1)" against normal blind 0.8 bodies 13 in component "PRINT registration seat 00"
ref_plane "WorkPlane5" through (0, 0, 5) normal (0, 0, 1) x (1, 0, 0) in component "PRINT registration seat 00"
sketch "Forward registration peg sketch (2)" plane through (0, 0, 5) normal (0, 0, 1) x (1, 0, 0) in component "PRINT registration seat 00"
  circle A0 centre (17, 7) radius 1
  dimension "d1344" = 17
  dimension "d1345" = 7
  dimension "d1346" = 2
  measures "d1344" horizontal distance of origin A0.centre
  measures "d1345" vertical distance of origin A0.centre
  measures "d1346" diameter of A0
extrude "Forward registration peg (2)" add sketch "Forward registration peg sketch (2)" against normal blind 0.8 bodies 13 in component "PRINT registration seat 00"
ref_plane "WorkPlane6" through (0, 0, 5) normal (0, 0, 1) x (1, 0, 0) in component "PRINT registration seat 00"
sketch "Forward registration peg sketch (3)" plane through (0, 0, 5) normal (0, 0, 1) x (1, 0, 0) in component "PRINT registration seat 00"
  circle A0 centre (17, 17) radius 1
  dimension "d1351" = 17
  dimension "d1352" = 17
  dimension "d1353" = 2
  measures "d1351" horizontal distance of origin A0.centre
  measures "d1352" vertical distance of origin A0.centre
  measures "d1353" diameter of A0
extrude "Forward registration peg (3)" add sketch "Forward registration peg sketch (3)" against normal blind 0.8 bodies 13 in component "PRINT registration seat 00"
sketch "8 mm shoulder sketch" plane through (0, 0, 0) normal (0, 0, 1) x (1, 0, 0) in component "METAL stepped compression spacer 00"
  circle A0 centre (12, 12) radius 4
  dimension "d1356" = 12
  dimension "d1357" = 12
  dimension "d1358" = 8
  measures "d1356" horizontal distance of origin A0.centre
  measures "d1357" vertical distance of origin A0.centre
  measures "d1358" diameter of A0
extrude "8 mm shoulder" add sketch "8 mm shoulder sketch" along normal blind 7 separate body makes body 14 in component "METAL stepped compression spacer 00"
ref_plane "WorkPlane1" through (0, 0, 7) normal (0, 0, 1) x (1, 0, 0) in component "METAL stepped compression spacer 00"
sketch "12 mm base sketch" plane through (0, 0, 7) normal (0, 0, 1) x (1, 0, 0) in component "METAL stepped compression spacer 00"
  circle A0 centre (12, 12) radius 6
  dimension "d1363" = 12
  dimension "d1364" = 12
  dimension "d1365" = 12
  measures "d1363" horizontal distance of origin A0.centre
  measures "d1364" vertical distance of origin A0.centre
  measures "d1365" diameter of A0
extrude "12 mm base" add sketch "12 mm base sketch" along normal blind 8 bodies 14 in component "METAL stepped compression spacer 00"
sketch "Through bore sketch" plane through (0, 0, 0) normal (0, 0, 1) x (1, 0, 0) in component "METAL stepped compression spacer 00"
  circle A0 centre (12, 12) radius 2.75
  dimension "d1368" = 12
  dimension "d1369" = 12
  dimension "d1370" = 5.5
  measures "d1368" horizontal distance of origin A0.centre
  measures "d1369" vertical distance of origin A0.centre
  measures "d1370" diameter of A0
extrude "Through bore" cut sketch "Through bore sketch" along normal blind 15 bodies 14 in component "METAL stepped compression spacer 00"
ref_plane "WorkPlane1" through (0, 0, -8) normal (0, 0, 1) x (1, 0, 0) in component "REFERENCE front M5x25 00"
sketch "Button head envelope sketch" plane through (0, 0, -8) normal (0, 0, 1) x (1, 0, 0) in component "REFERENCE front M5x25 00"
  circle A0 centre (12, 12) radius 4.75
  dimension "d1375" = 12
  dimension "d1376" = 12
  dimension "d1377" = 9.5
  measures "d1375" horizontal distance of origin A0.centre
  measures "d1376" vertical distance of origin A0.centre
  measures "d1377" diameter of A0
extrude "Button head envelope" add sketch "Button head envelope sketch" along normal blind 3 separate body makes body 15 in component "REFERENCE front M5x25 00"
ref_plane "WorkPlane2" through (0, 0, -5) normal (0, 0, 1) x (1, 0, 0) in component "REFERENCE front M5x25 00"
sketch "Shank envelope sketch" plane through (0, 0, -5) normal (0, 0, 1) x (1, 0, 0) in component "REFERENCE front M5x25 00"
  circle A0 centre (12, 12) radius 2.5
  dimension "d1382" = 12
  dimension "d1383" = 12
  dimension "d1384" = 5
  measures "d1382" horizontal distance of origin A0.centre
  measures "d1383" vertical distance of origin A0.centre
  measures "d1384" diameter of A0
extrude "Shank envelope" add sketch "Shank envelope sketch" along normal blind 25 bodies 15 in component "REFERENCE front M5x25 00"
ref_plane "WorkPlane1" through (0, 0, 16.5) normal (0, 0, 1) x (1, 0, 0) in component "REFERENCE thin METAL channel nut front 00"
sketch "Thin nut envelope sketch" plane through (0, 0, 16.5) normal (0, 0, 1) x (1, 0, 0) in component "REFERENCE thin METAL channel nut front 00"
  line L0 (7.6, 6) -> (16.4, 6)
  line L1 (16.4, 6) -> (16.4, 18)
  line L2 (16.4, 18) -> (7.6, 18)
  line L3 (7.6, 18) -> (7.6, 6)
  dimension "d1389" = 7.6
  dimension "d1390" = 6
  dimension "d1391" = 8.8
  dimension "d1392" = 12
  constraint horizontal L0
  constraint vertical L1
  constraint horizontal L2
  constraint vertical L3
  measures "d1389" horizontal distance of origin L0.start
  measures "d1390" vertical distance of origin L0.start
  measures "d1391" horizontal distance of L0.start L0.end
  measures "d1392" vertical distance of L0.end L1.end
extrude "Thin nut envelope" add sketch "Thin nut envelope sketch" along normal blind 2.7 separate body makes body 16 in component "REFERENCE thin METAL channel nut front 00"
ref_plane "WorkPlane2" through (0, 0, 16.5) normal (0, 0, 1) x (1, 0, 0) in component "REFERENCE thin METAL channel nut front 00"
sketch "Thread envelope sketch" plane through (0, 0, 16.5) normal (0, 0, 1) x (1, 0, 0) in component "REFERENCE thin METAL channel nut front 00"
  circle A0 centre (12, 12) radius 2.6
  dimension "d1397" = 12
  dimension "d1398" = 12
  dimension "d1399" = 5.2
  measures "d1397" horizontal distance of origin A0.centre
  measures "d1398" vertical distance of origin A0.centre
  measures "d1399" diameter of A0
extrude "Thread envelope" cut sketch "Thread envelope sketch" along normal blind 2.7 bodies 16 in component "REFERENCE thin METAL channel nut front 00"